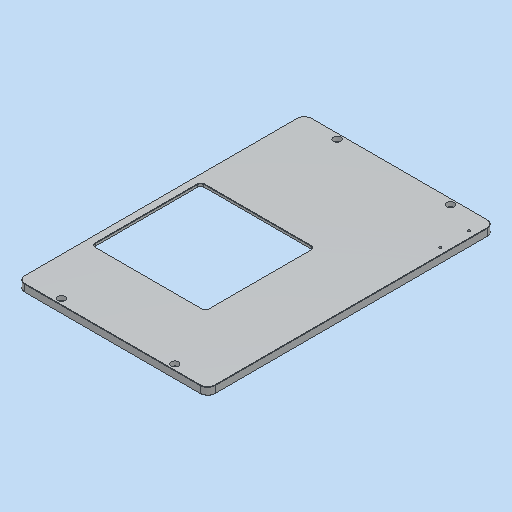
# Autodesk Inventor part: MM0948AN160_G01_102
Saved by Autodesk Inventor 2023.3 (Build 273359000, 359)
## iProperties
RuleStatus: InUse
Created: 2023-03-23
Part Number: MM0948AN160_G01_102
Material: 3.3547 AlMg4,5Mn0,7 - AW 5083
Description: =<RBPARTNOTITLE2>
Document SubType Name: Modeling
Designer: ric7an
Mass: 1904.42 g
Surface Area: 1664.83 cm^2
Volume: 715.947 cm^3
Density: 2.66 g/cm^3
Appearance: Aluminium AnP
AnP_Kategorie: 1
AnP_Material: =<Material>
MaxAbmaße: 10 x 380 x 252 (FM)
AnP_TemplVers: 20200821
RBDOCUMENTTYPE: DRF
RBDOCUMENTVERSION: 00
RBDRAWINGMAINSCALE: 1:1
RBDRAWINGMISSINGSPEC: --
RBDRAWINGVOLUME: --
RBDSV1: 0850
RBGBEDGESIN1: +0,5
RBGBEDGESIN2: +0,2
RBGBEDGESOUT1: -0,3
RBGBEDGESOUT2: -0,1
RBMATERIAL: =<Material>
RBMATMEETS: --
RBMATNO: =<Part Number>
RBPARTMADEOF: 10 x 380 x 252 (FM)
RBPARTNO: SIEHE MNR
RBPARTNOTITLE1: manufactured part
RBPARTNOTITLE2: Anfertigungsteil
RBPARTSAFETYINDICATOR: --
RBSURFACE: anodised colourless
RBSURFACE2: eloxiert farblos
RBZEDGESNORM: ISO13715:2002-06
RBZGENDIMCLASS: m
RBZGENDIMNORM: ISO 2768-1:1989-11
RBZGENGEOCLASS: H
RBZGENGEONORM: ISO 2768-2:1989-11
RBZSURFACENORM: ISO13D2:2002-02
RBZTOLERANCENORM: ISO 14405-1:2010-12
AnP_Kommentar_aktuell: =<Comments>
AnP_Material_aktuell: =<Material>
Author: FH/Wi
Keywords: =<RBPARTMADEOF>
Comments: =<RBSURFACE2>
Revision Number: 01
Autodesk Inventor part; units mm, degrees
ref_plane "YZ Plane" through (0, 0, 0) normal (1, 0, 0) x (0, 1, 0)
ref_plane "XZ Plane" through (0, 0, 0) normal (0, 1, 0) x (-1, 0, 0)
ref_plane "XY Plane" through (0, 0, 0) normal (0, 0, 1) x (1, 0, 0)
sketch "Skizze1" plane through (0, 0, 0) normal (0, 0, 1) x (1, 0, 0)
  line L0 (0, 0) -> (252, 0)
  line L1 (252, 0) -> (252, 380)
  line L2 (252, 380) -> (10, 380)
  line L3 (10, 233) -> (10, 89)
  line L4 (10, 233) -> (160, 233)
  line L5 (160, 233) -> (160, 89)
  line L6 (160, 89) -> (10, 89)
  line L7 (10, 89) -> (10, 233)
  line L8 (10, 380) -> (0, 380)
  line L9 (0, 380) -> (0, 0)
  line L10 (10, 233) -> (10, 380) construction
  line L11 (85, 233) -> (85, 89) construction
  line L12 (160, 161) -> (10, 161) construction
  point P0 (0, 89)
  point P1 (0, 45)
  dimension "d1" = 144
  dimension "d2" = 380
  dimension "d4" = 150
  dimension "d36" = 252
  dimension "d41" = 85
  dimension "d42" = 161
  constraints: 26 end point, 5 parallel, 4 midpoint, 3 horizontal, 3 perpendicular, 2 point on line
  measures "d1" distance of L4.end L5.end
  measures "d2" distance of L0.end L1.end
  measures "d4" distance of L3.end L5.end
  measures "d36" distance of L0.start L0.end
  measures "d41" distance between parallel lines of L9 L11
  measures "d42" distance between parallel lines of L0 L12
extrude "Extrusion1" add sketch "Skizze1" along normal blind 10
sketch "Skizze2" plane through (0, 0, 10) normal (0, 0, 1) x (1, 0, 0)
  line L0 (252, 380) -> (0, 380) projected
  line L1 (0, 0) -> (252, 0) projected
  line L2 (10, 89) -> (10, 0) projected
  line L3 (126, 380) -> (126, 237.4461)
  point P0 (51, 372.5)
  point P1 (201, 372.5)
  point P2 (201, 7.5)
  point P3 (51, 7.5)
  point P4 (0, 45)
  point P5 (10, 233)
  dimension "d8" = 150
  dimension "d9" = 7.5
  dimension "d10" = 7.5
  constraints: 2 end point, 2 horizontal alignment, 2 vertical alignment, 1 midpoint, 1 perpendicular, 1 symmetric about line, 1 other
  measures "d8" distance of point (201, 372.5) point (51, 372.5)
  measures "d9" distance from line of point (201, 372.5) L0
  measures "d10" distance from line of L1 point (201, 7.5)
hole "Bohrung1" at (51, 372.5, 10) at (201, 372.5, 10) at (201, 7.5, 10) at (51, 7.5, 10) direction (0, 0, -1) diameter 5.5 end through all counterbore diameter 10 counterbore depth 5.7 clearance for "Inbusschraube ISO 4762  versenkt" size "M5" standard "ISO"
sketch "Skizze4" plane through (0, 0, 0) normal (0, 0, -1) x (-1, 0, 0)
  line L0 (-160, 233) -> (-160, 89) projected
  line L1 (-10, 233) -> (-160, 233) projected
  line L2 (-10, 89) -> (-10, 233) projected
  line L3 (-160, 89) -> (-10, 89) projected
  line L4 (-166, 239) -> (-166, 83)
  line L5 (-166, 83) -> (-4, 83)
  line L6 (-4, 83) -> (-4, 239)
  line L7 (-4, 239) -> (-166, 239)
  point P0 (0, 0)
  dimension "d43" = 6
  constraints: 8 end point, 3 other
  measures "d43" distance between parallel lines of L0 L4
extrude "Extrusion2" cut sketch "Skizze4" against normal blind 6 contours L1 L2 L3 L0 | L7 L6 L5 L4
fillet "Rundung1" radius 4 8 edges at (160, 233, 8) (10, 233, 8) (10, 89, 8) (160, 89, 8) (4, 239, 3) (4, 83, 3) (166, 83, 3) (166, 239, 3)
fillet "Rundung1" radius 10 4 edges at (0, 380, 5) (252, 380, 5) (252, 0, 5) (0, 0, 5)
chamfer "Fase1" distance 0.5 angle 45 36 edges at (85, 233, 10) (2.9289, 2.9289, 10) (249.0711, 2.9289, 10) (2.9289, 377.0711, 10) (249.0711, 377.0711, 10) (160, 161, 10) (85, 89, 10) (10, 161, 10) (0, 190, 10) (126, 0, 10) (252, 190, 10) (126, 380, 10) (0, 190, 0) (2.9289, 2.9289, 0) (126, 0, 0) (249.0711, 2.9289, 0) (252, 190, 0) (249.0711, 377.0711, 0) (126, 380, 0) (2.9289, 377.0711, 0) (4, 161, 0) (5.1716, 84.1716, 0) (85, 83, 0) (164.8284, 84.1716, 0) (166, 161, 0) (164.8284, 237.8284, 0) (85, 239, 0) (5.1716, 237.8284, 0) (10, 161, 6) (11.1716, 231.8284, 6) (85, 233, 6) (158.8284, 231.8284, 6) (160, 161, 6) (158.8284, 90.1716, 6) (85, 89, 6) (11.1716, 90.1716, 6)
sketch "Skizze5" plane through (0, 0, 10) normal (0, 0, 1) x (1, 0, 0)
  line L0 (252, 10) -> (252, 370) projected
  line L1 (10, 0) -> (242, 0) projected
  line L2 (242, 380) -> (10, 380) projected
  point P0 (0, 0)
  point P1 (243, 317)
  point P2 (243, 355)
  dimension "d47" = 38
  dimension "d48" = 9
  dimension "d57" = 25
  constraints: 1 vertical alignment
  measures "d47" distance of point (243, 317) point (243, 355)
  measures "d48" distance from line of L0 point (243, 317)
  measures "d57" distance from line of L2 point (243, 355)
hole "Bohrung3" at (243, 317, 10) at (243, 355, 10) direction (0, 0, -1) diameter 3.242 end through all thread size "M4x0.7" designation "M4" class "6H" standard "ISO Metric profile"
equation "\"d10\" = d9"
